Autodesk Fusion 360 part; units mm, degrees
(part 2 of 18)
sketch "8x8-User_Drawings" plane through (0, 0, 0) normal (0, 0, 1) x (1, 0, 0)
  line L0 (119.511, -144.623) -> (118.963, -144.827)
  line L1 (121.059, -143.805) -> (120.561, -144.111)
  line L2 (120.561, -144.111) -> (120.044, -144.384)
  line L3 (124.456, -132.831) -> (124.659, -133.378)
  line L4 (121.99, -143.101) -> (121.536, -143.468)
  line L5 (122.823, -142.282) -> (122.42, -142.705)
  line L6 (121.536, -143.468) -> (121.059, -143.805)
  line L7 (55.9045, -129.451) -> (55.4411, -129.079)
  line L8 (55.4411, -129.079) -> (54.954, -128.74)
  line L9 (54.4456, -128.433) -> (53.9179, -128.161)
  line L10 (54.954, -128.74) -> (54.4456, -128.433)
  line L11 (57.8006, -131.718) -> (57.4833, -131.217)
  line L12 (58.084, -132.24) -> (57.8006, -131.718)
  line L13 (57.4833, -131.217) -> (57.1334, -130.737)
  line L14 (57.1334, -130.737) -> (56.7525, -130.281)
  line L15 (56.3423, -129.852) -> (55.9045, -129.451)
  line L16 (123.544, -141.363) -> (123.199, -141.834)
  line L17 (56.7525, -130.281) -> (56.3423, -129.852)
  line L18 (124.218, -132.297) -> (124.456, -132.831)
  line L19 (53.9179, -128.161) -> (53.3734, -127.924)
  line L20 (53.3734, -127.924) -> (52.8143, -127.724)
  line L21 (52.2432, -127.561) -> (51.6626, -127.437)
  line L22 (56.453, -142.538) -> (56.8557, -142.101)
  line L23 (85.6834, -62.0285) -> (85.495, -62.5917)
  line L24 (52.8143, -127.724) -> (52.2432, -127.561)
  line L25 (123.858, -140.87) -> (123.544, -141.363)
  line L26 (56.8557, -142.101) -> (57.2286, -141.639)
  line L27 (58.3321, -132.78) -> (58.084, -132.24)
  line L28 (55.0844, -143.674) -> (55.5654, -143.326)
  line L29 (107.078, -135.288) -> (107.159, -134.71)
  line L30 (123.199, -141.834) -> (122.823, -142.282)
  line L31 (53.5182, -144.517) -> (54.0585, -144.271)
  line L32 (54.5813, -143.99) -> (55.0844, -143.674)
  line L33 (52.3945, -144.9) -> (52.9627, -144.727)
  line L34 (52.9627, -144.727) -> (53.5182, -144.517)
  line L35 (113.386, -127.609) -> (113.949, -127.454)
  line L36 (51.8162, -145.034) -> (52.3945, -144.9)
  line L37 (85.2321, -63.7491) -> (85.1587, -64.3384)
  line L38 (51.2302, -145.13) -> (51.8162, -145.034)
  line L39 (54.0585, -144.271) -> (54.5813, -143.99)
  line L40 (115.099, -127.253) -> (115.682, -127.209)
  line L41 (58.5935, -139.017) -> (58.7582, -138.447)
  line L42 (58.7582, -138.447) -> (58.8847, -137.867)
  line L43 (58.9725, -137.279) -> (59.0211, -136.687)
  line L44 (55.5654, -143.326) -> (56.0223, -142.947)
  line L45 (85.495, -62.5917) -> (85.3443, -63.166)
  line L46 (58.8847, -137.867) -> (58.9725, -137.279)
  line L47 (85.3443, -63.166) -> (85.2321, -63.7491)
  line L48 (56.0223, -142.947) -> (56.453, -142.538)
  line L49 (112.834, -127.801) -> (113.386, -127.609)
  line L50 (57.8785, -140.646) -> (58.1527, -140.119)
  line L51 (57.2286, -141.639) -> (57.57, -141.153)
  line L52 (57.57, -141.153) -> (57.8785, -140.646)
  line L53 (114.521, -127.335) -> (115.099, -127.253)
  line L54 (122.42, -142.705) -> (121.99, -143.101)
  line L55 (120.044, -144.384) -> (119.511, -144.623)
  line L56 (58.1527, -140.119) -> (58.3914, -139.576)
  line L57 (51.075, -127.351) -> (50.483, -127.304)
  line L58 (50.483, -127.304) -> (49.8893, -127.297)
  line L59 (124.781, -138.729) -> (124.602, -139.286)
  line L60 (125.125, -136.424) -> (125.095, -137.007)
  line L61 (43.5489, -130.12) -> (43.157, -130.566)
  line L62 (123.304, -130.804) -> (123.641, -131.281)
  line L63 (125.027, -137.588) -> (124.922, -138.162)
  line L64 (58.3914, -139.576) -> (58.5935, -139.017)
  line L65 (123.641, -131.281) -> (123.946, -131.78)
  line L66 (124.659, -133.378) -> (124.827, -133.938)
  line L67 (124.14, -140.359) -> (123.858, -140.87)
  line L68 (108.402, -131.454) -> (108.727, -130.969)
  line L69 (108.727, -130.969) -> (109.084, -130.506)
  line L70 (109.469, -130.066) -> (109.882, -129.653)
  line L71 (109.084, -130.506) -> (109.469, -130.066)
  line L72 (41.6834, -133.129) -> (41.495, -133.692)
  line L73 (41.9088, -132.579) -> (41.6834, -133.129)
  line L74 (107.432, -133.574) -> (107.622, -133.022)
  line L75 (107.622, -133.022) -> (107.848, -132.483)
  line L76 (108.108, -131.96) -> (108.402, -131.454)
  line L77 (109.882, -129.653) -> (110.32, -129.267)
  line L78 (110.32, -129.267) -> (110.783, -128.91)
  line L79 (110.783, -128.91) -> (111.268, -128.584)
  line L80 (107.848, -132.483) -> (108.108, -131.96)
  line L81 (111.268, -128.584) -> (111.772, -128.289)
  line L82 (121.673, -129.138) -> (122.121, -129.514)
  line L83 (59.0121, -135.657) -> (58.9531, -135.066)
  line L84 (58.8551, -134.48) -> (58.7185, -133.902)
  line L85 (59.0211, -136.687) -> (59.0318, -136.25)
  line L86 (59.0318, -136.25) -> (59.0121, -135.657)
  line L87 (58.5439, -133.335) -> (58.3321, -132.78)
  line L88 (58.7185, -133.902) -> (58.5439, -133.335)
  line L89 (58.9531, -135.066) -> (58.8551, -134.48)
  line L90 (122.543, -129.918) -> (122.938, -130.349)
  line L91 (43.9695, -129.701) -> (43.5489, -130.12)
  line L92 (125.051, -135.084) -> (125.108, -135.666)
  line L93 (124.957, -134.508) -> (125.051, -135.084)
  line L94 (125.108, -135.666) -> (125.127, -136.25)
  line L95 (41.1587, -135.438) -> (41.1245, -136.031)
  line L96 (41.2321, -134.849) -> (41.1587, -135.438)
  line L97 (41.3443, -134.266) -> (41.2321, -134.849)
  line L98 (41.495, -133.692) -> (41.3443, -134.266)
  line L99 (125.127, -136.25) -> (125.125, -136.424)
  line L100 (124.602, -139.286) -> (124.389, -139.83)
  line L101 (122.121, -129.514) -> (122.543, -129.918)
  line L102 (120.199, -128.194) -> (120.711, -128.476)
  line L103 (43.157, -130.566) -> (42.7955, -131.037)
  line L104 (119.128, -127.73) -> (119.671, -127.944)
  line L105 (41.1297, -136.625) -> (41.1742, -137.217)
  line L106 (111.772, -128.289) -> (112.295, -128.028)
  line L107 (51.6626, -127.437) -> (51.075, -127.351)
  line L108 (113.949, -127.454) -> (114.521, -127.335)
  line L109 (107.159, -134.71) -> (107.277, -134.137)
  line L110 (122.938, -130.349) -> (123.304, -130.804)
  line L111 (107.277, -134.137) -> (107.432, -133.574)
  line L112 (123.946, -131.78) -> (124.218, -132.297)
  line L113 (124.827, -133.938) -> (124.957, -134.508)
  line L114 (124.922, -138.162) -> (124.781, -138.729)
  line L115 (46.4345, -128.069) -> (45.9003, -128.329)
  line L116 (47.5484, -127.659) -> (46.9847, -127.846)
  line L117 (42.466, -131.531) -> (42.17, -132.046)
  line L118 (45.3845, -128.623) -> (44.8893, -128.951)
  line L119 (121.203, -128.792) -> (121.673, -129.138)
  line L120 (86.17, -60.9459) -> (85.9088, -61.4791)
  line L121 (46.9847, -127.846) -> (46.4345, -128.069)
  line L122 (117.43, -127.302) -> (118.005, -127.408)
  line L123 (116.85, -127.233) -> (117.43, -127.302)
  line L124 (42.17, -132.046) -> (41.9088, -132.579)
  line L125 (125.095, -137.007) -> (125.027, -137.588)
  line L126 (41.1245, -136.031) -> (41.1297, -136.625)
  line L127 (118.005, -127.408) -> (118.571, -127.551)
  line L128 (45.9003, -128.329) -> (45.3845, -128.623)
  line L129 (116.266, -127.202) -> (116.85, -127.233)
  line L130 (124.389, -139.83) -> (124.14, -140.359)
  line L131 (44.8893, -128.951) -> (44.417, -129.31)
  line L132 (48.1233, -127.511) -> (47.5484, -127.659)
  line L133 (112.295, -128.028) -> (112.834, -127.801)
  line L134 (49.2963, -127.329) -> (48.7068, -127.4)
  line L135 (119.671, -127.944) -> (120.199, -128.194)
  line L136 (49.8893, -127.297) -> (49.2963, -127.329)
  line L137 (115.682, -127.209) -> (116.266, -127.202)
  line L138 (86.466, -60.4311) -> (86.17, -60.9459)
  line L139 (120.711, -128.476) -> (121.203, -128.792)
  line L140 (48.7068, -127.4) -> (48.1233, -127.511)
  line L141 (44.417, -129.31) -> (43.9695, -129.701)
  line L142 (42.7955, -131.037) -> (42.466, -131.531)
  line L143 (85.9088, -61.4791) -> (85.6834, -62.0285)
  line L144 (118.571, -127.551) -> (119.128, -127.73)
  line L145 (120.446, -128.433) -> (119.918, -128.161)
  line L146 (122.856, -142.101) -> (123.229, -141.639)
  line L147 (123.57, -141.153) -> (123.879, -140.646)
  line L148 (123.879, -140.646) -> (124.153, -140.119)
  line L149 (121.441, -129.079) -> (120.954, -128.74)
  line L150 (120.954, -128.74) -> (120.446, -128.433)
  line L151 (123.229, -141.639) -> (123.57, -141.153)
  line L152 (121.904, -129.451) -> (121.441, -129.079)
  line L153 (107.382, -138.76) -> (107.238, -138.193)
  line L154 (122.342, -129.852) -> (121.904, -129.451)
  line L155 (125.032, -136.25) -> (125.012, -135.657)
  line L156 (125.021, -136.687) -> (125.032, -136.25)
  line L157 (124.391, -139.576) -> (124.594, -139.017)
  line L158 (124.153, -140.119) -> (124.391, -139.576)
  line L159 (124.594, -139.017) -> (124.758, -138.447)
  line L160 (124.972, -137.279) -> (125.021, -136.687)
  line L161 (117.816, -145.034) -> (118.395, -144.9)
  line L162 (122.453, -142.538) -> (122.856, -142.101)
  line L163 (109.657, -142.493) -> (110.085, -142.905)
  line L164 (124.885, -137.867) -> (124.972, -137.279)
  line L165 (114.276, -145.022) -> (114.861, -145.122)
  line L166 (115.452, -145.183) -> (116.046, -145.205)
  line L167 (116.046, -145.205) -> (116.639, -145.187)
  line L168 (110.539, -143.287) -> (111.018, -143.639)
  line L169 (110.085, -142.905) -> (110.539, -143.287)
  line L170 (114.861, -145.122) -> (115.452, -145.183)
  line L171 (123.133, -130.737) -> (122.753, -130.281)
  line L172 (124.758, -138.447) -> (124.885, -137.867)
  line L173 (117.23, -145.13) -> (117.816, -145.034)
  line L174 (116.639, -145.187) -> (117.23, -145.13)
  line L175 (111.518, -143.958) -> (112.039, -144.243)
  line L176 (108.311, -140.898) -> (108.028, -140.387)
  line L177 (108.028, -140.387) -> (107.777, -139.859)
  line L178 (120.581, -143.99) -> (121.084, -143.674)
  line L179 (123.483, -131.217) -> (123.133, -130.737)
  line L180 (107.777, -139.859) -> (107.562, -139.316)
  line L181 (108.627, -141.389) -> (108.311, -140.898)
  line L182 (124.719, -133.902) -> (124.544, -133.335)
  line L183 (108.975, -141.859) -> (108.627, -141.389)
  line L184 (125.012, -135.657) -> (124.953, -135.066)
  line L185 (120.059, -144.271) -> (120.581, -143.99)
  line L186 (108.55, -141.101) -> (108.888, -141.589)
  line L187 (113.132, -144.707) -> (113.699, -144.883)
  line L188 (122.022, -142.947) -> (122.453, -142.538)
  line L189 (112.039, -144.243) -> (112.578, -144.493)
  line L190 (112.672, -144.635) -> (112.138, -144.398)
  line L191 (119.518, -144.517) -> (120.059, -144.271)
  line L192 (108.245, -140.591) -> (108.55, -141.101)
  line L193 (110.187, -143.121) -> (109.756, -142.727)
  line L194 (113.22, -144.837) -> (112.672, -144.635)
  line L195 (109.351, -142.306) -> (108.975, -141.859)
  line L196 (111.018, -143.639) -> (111.518, -143.958)
  line L197 (113.699, -144.883) -> (114.276, -145.022)
  line L198 (118.963, -144.727) -> (119.518, -144.517)
  line L199 (110.643, -143.487) -> (110.187, -143.121)
  line L200 (124.855, -134.48) -> (124.719, -133.902)
  line L201 (107.562, -139.316) -> (107.382, -138.76)
  line L202 (123.801, -131.718) -> (123.483, -131.217)
  line L203 (112.138, -144.398) -> (111.62, -144.127)
  line L204 (107.258, -137.805) -> (107.38, -138.386)
  line L205 (114.35, -145.134) -> (113.78, -145.004)
  line L206 (121.084, -143.674) -> (121.565, -143.326)
  line L207 (124.084, -132.24) -> (123.801, -131.718)
  line L208 (107.131, -137.619) -> (107.061, -137.039)
  line L209 (111.62, -144.127) -> (111.121, -143.823)
  line L210 (108.888, -141.589) -> (109.257, -142.054)
  line L211 (124.953, -135.066) -> (124.855, -134.48)
  line L212 (109.257, -142.054) -> (109.657, -142.493)
  line L213 (117.835, -145.128) -> (117.258, -145.223)
  line L214 (116.677, -145.28) -> (116.093, -145.3)
  line L215 (117.258, -145.223) -> (116.677, -145.28)
  line L216 (121.565, -143.326) -> (122.022, -142.947)
  line L217 (115.509, -145.282) -> (114.927, -145.227)
  line L218 (107.174, -137.217) -> (107.258, -137.805)
  line L219 (116.093, -145.3) -> (115.509, -145.282)
  line L220 (107.029, -136.455) -> (107.033, -136.031)
  line L221 (107.061, -137.039) -> (107.029, -136.455)
  line L222 (112.578, -144.493) -> (113.132, -144.707)
  line L223 (118.395, -144.9) -> (118.963, -144.727)
  line L224 (109.756, -142.727) -> (109.351, -142.306)
  line L225 (113.78, -145.004) -> (113.22, -144.837)
  line L226 (114.927, -145.227) -> (114.35, -145.134)
  line L227 (122.753, -130.281) -> (122.342, -129.852)
  line L228 (107.035, -135.871) -> (107.078, -135.288)
  line L229 (107.541, -138.958) -> (107.739, -139.517)
  line L230 (118.404, -144.996) -> (117.835, -145.128)
  line L231 (124.332, -132.78) -> (124.084, -132.24)
  line L232 (107.38, -138.386) -> (107.541, -138.958)
  line L233 (111.121, -143.823) -> (110.643, -143.487)
  line L234 (124.544, -133.335) -> (124.332, -132.78)
  line L235 (107.033, -136.031) -> (107.035, -135.871)
  line L236 (107.974, -140.063) -> (108.245, -140.591)
  line L237 (118.963, -144.827) -> (118.404, -144.996)
  line L238 (107.739, -139.517) -> (107.974, -140.063)
  line L239 (107.238, -138.193) -> (107.131, -137.619)
  line L240 (109.97, -129.701) -> (109.549, -130.12)
  line L241 (118.814, -127.724) -> (118.243, -127.561)
  line L242 (109.549, -130.12) -> (109.157, -130.566)
  line L243 (130.108, -131.96) -> (130.402, -131.454)
  line L244 (130.402, -131.454) -> (130.727, -130.969)
  line L245 (110.417, -129.31) -> (109.97, -129.701)
  line L246 (129.848, -132.483) -> (130.108, -131.96)
  line L247 (111.9, -128.329) -> (111.385, -128.623)
  line L248 (129.432, -133.574) -> (129.622, -133.022)
  line L249 (111.385, -128.623) -> (110.889, -128.951)
  line L250 (114.707, -127.4) -> (114.123, -127.511)
  line L251 (129.277, -134.137) -> (129.432, -133.574)
  line L252 (112.434, -128.069) -> (111.9, -128.329)
  line L253 (108.466, -131.531) -> (108.17, -132.046)
  line L254 (107.909, -132.579) -> (107.683, -133.129)
  line L255 (108.795, -131.037) -> (108.466, -131.531)
  line L256 (115.296, -127.329) -> (114.707, -127.4)
  line L257 (112.985, -127.846) -> (112.434, -128.069)
  line L258 (129.622, -133.022) -> (129.848, -132.483)
  line L259 (129.159, -134.71) -> (129.277, -134.137)
  line L260 (119.918, -128.161) -> (119.373, -127.924)
  line L261 (119.373, -127.924) -> (118.814, -127.724)
  line L262 (110.889, -128.951) -> (110.417, -129.31)
  line L263 (107.13, -136.625) -> (107.174, -137.217)
  line L264 (115.889, -127.297) -> (115.296, -127.329)
  line L265 (107.683, -133.129) -> (107.495, -133.692)
  line L266 (107.232, -134.849) -> (107.159, -135.438)
  line L267 (129.078, -135.288) -> (129.159, -134.71)
  line L268 (118.243, -127.561) -> (117.663, -127.437)
  line L269 (114.123, -127.511) -> (113.548, -127.659)
  line L270 (117.075, -127.351) -> (116.483, -127.304)
  line L271 (107.344, -134.266) -> (107.232, -134.849)
  line L272 (108.17, -132.046) -> (107.909, -132.579)
  line L273 (116.483, -127.304) -> (115.889, -127.297)
  line L274 (113.548, -127.659) -> (112.985, -127.846)
  line L275 (117.663, -127.437) -> (117.075, -127.351)
  line L276 (109.157, -130.566) -> (108.795, -131.037)
  line L277 (107.159, -135.438) -> (107.124, -136.031)
  line L278 (107.124, -136.031) -> (107.13, -136.625)
  line L279 (107.495, -133.692) -> (107.344, -134.266)
  line L280 (100.342, -58.7519) -> (99.9045, -58.3507)
  line L281 (89.9003, -57.2286) -> (89.3845, -57.5228)
  line L282 (96.2432, -56.461) -> (95.6626, -56.3365)
  line L283 (94.483, -56.2042) -> (93.8893, -56.197)
  line L284 (96.8143, -56.6237) -> (96.2432, -56.461)
  line L285 (90.4345, -56.9692) -> (89.9003, -57.2286)
  line L286 (95.075, -56.2508) -> (94.483, -56.2042)
  line L287 (99.9045, -58.3507) -> (99.4411, -57.9794)
  line L288 (99.4411, -57.9794) -> (98.954, -57.6397)
  line L289 (86.7955, -59.9371) -> (86.466, -60.4311)
  line L290 (90.9847, -56.7458) -> (90.4345, -56.9692)
  line L291 (87.157, -59.466) -> (86.7955, -59.9371)
  line L292 (97.3734, -56.8239) -> (96.8143, -56.6237)
  line L293 (88.8893, -57.8505) -> (88.417, -58.2104)
  line L294 (89.3845, -57.5228) -> (88.8893, -57.8505)
  line L295 (98.954, -57.6397) -> (98.4456, -57.333)
  line L296 (95.6626, -56.3365) -> (95.075, -56.2508)
  line L297 (87.9695, -58.6007) -> (87.5489, -59.0199)
  line L298 (93.2963, -56.2291) -> (92.7068, -56.3004)
  line L299 (91.5484, -56.5593) -> (90.9847, -56.7458)
  line L300 (92.1233, -56.4107) -> (91.5484, -56.5593)
  line L301 (97.9179, -57.0606) -> (97.3734, -56.8239)
  line L302 (98.4456, -57.333) -> (97.9179, -57.0606)
  line L303 (87.5489, -59.0199) -> (87.157, -59.466)
  line L304 (88.417, -58.2104) -> (87.9695, -58.6007)
  line L305 (93.8893, -56.197) -> (93.2963, -56.2291)
  line L306 (92.7068, -56.3004) -> (92.1233, -56.4107)
  line L307 (142.044, -144.384) -> (141.511, -144.623)
  line L308 (146.957, -134.508) -> (147.051, -135.084)
  line L309 (147.027, -137.588) -> (146.922, -138.162)
  line L310 (147.108, -135.666) -> (147.127, -136.25)
  line L311 (140.571, -127.551) -> (141.128, -127.73)
  line L312 (145.304, -130.804) -> (145.641, -131.281)
  line L313 (145.946, -131.78) -> (146.218, -132.297)
  line L314 (146.218, -132.297) -> (146.456, -132.831)
  line L315 (145.641, -131.281) -> (145.946, -131.78)
  line L316 (146.659, -133.378) -> (146.827, -133.938)
  line L317 (135.949, -127.454) -> (136.521, -127.335)
  line L318 (137.099, -127.253) -> (137.682, -127.209)
  line L319 (138.85, -127.233) -> (139.43, -127.302)
  line L320 (133.268, -128.584) -> (133.772, -128.289)
  line L321 (130.727, -130.969) -> (131.084, -130.506)
  line L322 (146.922, -138.162) -> (146.781, -138.729)
  line L323 (143.673, -129.138) -> (144.121, -129.514)
  line L324 (147.125, -136.424) -> (147.095, -137.007)
  line L325 (141.511, -144.623) -> (140.963, -144.827)
  line L326 (144.938, -130.349) -> (145.304, -130.804)
  line L327 (144.121, -129.514) -> (144.543, -129.918)
  line L328 (146.389, -139.83) -> (146.14, -140.359)
  line L329 (144.543, -129.918) -> (144.938, -130.349)
  line L330 (146.14, -140.359) -> (145.858, -140.87)
  line L331 (138.266, -127.202) -> (138.85, -127.233)
  line L332 (141.128, -127.73) -> (141.671, -127.944)
  line L333 (135.386, -127.609) -> (135.949, -127.454)
  line L334 (134.295, -128.028) -> (134.834, -127.801)
  line L335 (144.823, -142.282) -> (144.42, -142.705)
  line L336 (144.42, -142.705) -> (143.99, -143.101)
  line L337 (145.858, -140.87) -> (145.544, -141.363)
  line L338 (147.051, -135.084) -> (147.108, -135.666)
  line L339 (143.203, -128.792) -> (143.673, -129.138)
  line L340 (146.827, -133.938) -> (146.957, -134.508)
  line L341 (140.005, -127.408) -> (140.571, -127.551)
  line L342 (143.99, -143.101) -> (143.536, -143.468)
  line L343 (147.095, -137.007) -> (147.027, -137.588)
  line L344 (142.711, -128.476) -> (143.203, -128.792)
  line L345 (147.127, -136.25) -> (147.125, -136.424)
  line L346 (146.602, -139.286) -> (146.389, -139.83)
  line L347 (142.199, -128.194) -> (142.711, -128.476)
  line L348 (142.561, -144.111) -> (142.044, -144.384)
  line L349 (137.682, -127.209) -> (138.266, -127.202)
  line L350 (139.43, -127.302) -> (140.005, -127.408)
  line L351 (146.781, -138.729) -> (146.602, -139.286)
  line L352 (146.456, -132.831) -> (146.659, -133.378)
  line L353 (134.834, -127.801) -> (135.386, -127.609)
  line L354 (136.521, -127.335) -> (137.099, -127.253)
  line L355 (131.882, -129.653) -> (132.32, -129.267)
  line L356 (143.536, -143.468) -> (143.059, -143.805)
  line L357 (131.469, -130.066) -> (131.882, -129.653)
  line L358 (132.32, -129.267) -> (132.783, -128.91)
  line L359 (145.544, -141.363) -> (145.199, -141.834)
  line L360 (131.084, -130.506) -> (131.469, -130.066)
  line L361 (141.671, -127.944) -> (142.199, -128.194)
  line L362 (145.199, -141.834) -> (144.823, -142.282)
  line L363 (132.783, -128.91) -> (133.268, -128.584)
  line L364 (143.059, -143.805) -> (142.561, -144.111)
  line L365 (133.772, -128.289) -> (134.295, -128.028)
  line L366 (101.133, -59.6368) -> (100.753, -59.1812)
  line L367 (103.012, -64.5565) -> (102.953, -63.9656)
  line L368 (100.453, -71.4378) -> (100.856, -71.0014)
  line L369 (102.332, -61.6798) -> (102.084, -61.1403)
  line L370 (97.5182, -73.4173) -> (98.0585, -73.1711)
  line L371 (93.4521, -74.0832) -> (94.0455, -74.1049)
  line L372 (94.6391, -74.0873) -> (95.2302, -74.0304)
  line L373 (102.953, -63.9656) -> (102.855, -63.38)
  line L374 (103.032, -65.15) -> (103.012, -64.5565)
  line L375 (96.9627, -73.6272) -> (97.5182, -73.4173)
  line L376 (102.719, -62.8021) -> (102.544, -62.2345)
  line L377 (101.229, -70.5393) -> (101.57, -70.0534)
  line L378 (100.753, -59.1812) -> (100.342, -58.7519)
  line L379 (100.856, -71.0014) -> (101.229, -70.5393)
  line L380 (102.758, -67.3467) -> (102.885, -66.7665)
  line L381 (96.3945, -73.7999) -> (96.9627, -73.6272)
  line L382 (99.0844, -72.574) -> (99.5654, -72.2258)
  line L383 (102.594, -67.9172) -> (102.758, -67.3467)
  line L384 (101.879, -69.546) -> (102.153, -69.0193)
  line L385 (99.5654, -72.2258) -> (100.022, -71.8465)
  line L386 (102.084, -61.1403) -> (101.801, -60.6185)
  line L387 (102.972, -66.1793) -> (103.021, -65.5875)
  line L388 (101.57, -70.0534) -> (101.879, -69.546)
  line L389 (102.391, -68.4756) -> (102.594, -67.9172)
  line L390 (102.544, -62.2345) -> (102.332, -61.6798)
  line L391 (102.855, -63.38) -> (102.719, -62.8021)
  line L392 (98.0585, -73.1711) -> (98.5813, -72.8896)
  line L393 (102.885, -66.7665) -> (102.972, -66.1793)
  line L394 (95.8162, -73.9345) -> (96.3945, -73.7999)
  line L395 (101.801, -60.6185) -> (101.483, -60.1165)
  line L396 (103.021, -65.5875) -> (103.032, -65.15)
  line L397 (95.2302, -74.0304) -> (95.8162, -73.9345)
  line L398 (102.153, -69.0193) -> (102.391, -68.4756)
  line L399 (94.0455, -74.1049) -> (94.6391, -74.0873)
  line L400 (101.483, -60.1165) -> (101.133, -59.6368)
  line L401 (98.5813, -72.8896) -> (99.0844, -72.574)
  line L402 (100.022, -71.8465) -> (100.453, -71.4378)
  line L403 (91.6987, -73.7835) -> (92.2761, -73.9221)
  line L404 (91.1318, -73.6069) -> (91.6987, -73.7835)
  line L405 (92.2761, -73.9221) -> (92.8615, -74.0221)
  line L406 (92.8615, -74.0221) -> (93.4521, -74.0832)
  line L407 (85.0332, -64.9312) -> (85.0347, -64.771)
  line L408 (85.3803, -67.2861) -> (85.541, -67.8577)
  line L409 (85.2578, -66.705) -> (85.3803, -67.2861)
  line L410 (91.9488, -56.3538) -> (92.5208, -56.2348)
  line L411 (85.3817, -67.6597) -> (85.2379, -67.0934)
  line L412 (85.9741, -68.9629) -> (86.2446, -69.4915)
  line L413 (94.2663, -56.102) -> (94.8498, -56.1331)
  line L414 (85.0612, -65.9388) -> (85.0291, -65.3553)
  line L415 (86.0276, -69.2867) -> (85.7774, -68.7587)
  line L416 (90.2951, -56.928) -> (90.8336, -56.7011)
  line L417 (93.0994, -56.1529) -> (93.682, -56.1086)
  line L418 (89.7724, -57.1892) -> (90.2951, -56.928)
  line L419 (90.5778, -73.3931) -> (91.1318, -73.6069)
  line L420 (85.1309, -66.5189) -> (85.0612, -65.9388)
  line L421 (91.3856, -56.5094) -> (91.9488, -56.3538)
  line L422 (86.2446, -69.4915) -> (86.5495, -70.001)
  line L423 (85.7774, -68.7587) -> (85.5618, -68.2156)
  line L424 (19.9088, -61.4791) -> (19.6834, -62.0285)
  line L425 (90.0392, -73.1431) -> (90.5778, -73.3931)
  line L426 (86.3113, -69.7975) -> (86.0276, -69.2867)
  line L427 (87.6569, -71.3931) -> (88.0847, -71.8049)
  line L428 (88.0847, -71.8049) -> (88.539, -72.1873)
  line L429 (92.5208, -56.2348) -> (93.0994, -56.1529)
  line L430 (85.1742, -66.1171) -> (85.2578, -66.705)
  line L431 (20.466, -60.4311) -> (20.17, -60.9459)
  line L432 (20.17, -60.9459) -> (19.9088, -61.4791)
  line L433 (88.539, -72.1873) -> (89.0175, -72.5389)
  line L434 (86.8876, -70.4892) -> (87.2572, -70.9539)
  line L435 (86.5495, -70.001) -> (86.8876, -70.4892)
  line L436 (85.0291, -65.3553) -> (85.0332, -64.9312)
  line L437 (89.0175, -72.5389) -> (89.5183, -72.8579)
  line L438 (85.541, -67.8577) -> (85.7392, -68.4175)
  line L439 (85.7392, -68.4175) -> (85.9741, -68.9629)
  line L440 (89.5183, -72.8579) -> (90.0392, -73.1431)
  line L441 (85.2379, -67.0934) -> (85.1309, -66.5189)
  line L442 (90.8336, -56.7011) -> (91.3856, -56.5094)
  line L443 (87.2572, -70.9539) -> (87.6569, -71.3931)
  line L444 (85.5618, -68.2156) -> (85.3817, -67.6597)
  line L445 (94.8498, -56.1331) -> (95.4301, -56.2018)
  line L446 (85.0347, -64.771) -> (85.078, -64.1883)
  line L447 (93.682, -56.1086) -> (94.2663, -56.102)
  line L448 (85.4315, -62.4738) -> (85.6222, -61.9215)
  line L449 (88.7829, -57.8099) -> (89.2676, -57.4835)
  line L450 (129.159, -64.3384) -> (129.124, -64.9312)
  line L451 (85.6222, -61.9215) -> (85.8482, -61.3827)
  line L452 (85.2769, -63.0373) -> (85.4315, -62.4738)
  line L453 (85.1589, -63.6096) -> (85.2769, -63.0373)
  line L454 (129.124, -64.9312) -> (129.13, -65.525)
  line L455 (87.8816, -58.5528) -> (88.3203, -58.1668)
  line L456 (89.2676, -57.4835) -> (89.7724, -57.1892)
  line L457 (88.3203, -58.1668) -> (88.7829, -57.8099)
  line L458 (129.232, -63.7491) -> (129.159, -64.3384)
  line L459 (85.078, -64.1883) -> (85.1589, -63.6096)
  line L460 (87.0836, -59.4057) -> (87.4688, -58.9664)
  line L461 (87.4688, -58.9664) -> (87.8816, -58.5528)
  line L462 (86.1085, -60.8595) -> (86.402, -60.3542)
  line L463 (86.402, -60.3542) -> (86.7274, -59.869)
  line L464 (129.13, -65.525) -> (129.174, -66.1171)
  line L465 (85.8482, -61.3827) -> (86.1085, -60.8595)
  line L466 (86.7274, -59.869) -> (87.0836, -59.4057)
  line L467 (129.344, -63.166) -> (129.232, -63.7491)
  line L468 (98.1995, -57.0936) -> (98.7108, -57.3764)
  line L469 (129.909, -61.4791) -> (129.683, -62.0285)
  line L470 (129.683, -62.0285) -> (129.495, -62.5917)
  line L471 (96.5713, -56.4506) -> (97.1275, -56.6297)
  line L472 (98.7108, -57.3764) -> (99.2028, -57.6917)
  line L473 (99.2028, -57.6917) -> (99.6734, -58.038)
  line L474 (129.495, -62.5917) -> (129.344, -63.166)
  line L475 (97.671, -56.8443) -> (98.1995, -57.0936)
  line L476 (97.1275, -56.6297) -> (97.671, -56.8443)
  line L477 (130.17, -60.9459) -> (129.909, -61.4791)
  line L478 (131.549, -59.0199) -> (131.157, -59.466)
  line L479 (96.0047, -56.3077) -> (96.5713, -56.4506)
  line L480 (132.417, -58.2104) -> (131.97, -58.6007)
  line L481 (130.795, -59.9371) -> (130.466, -60.4311)
  line L482 (95.4301, -56.2018) -> (96.0047, -56.3077)
  line L483 (131.97, -58.6007) -> (131.549, -59.0199)
  line L484 (130.466, -60.4311) -> (130.17, -60.9459)
  line L485 (131.157, -59.466) -> (130.795, -59.9371)
  line L486 (132.889, -57.8505) -> (132.417, -58.2104)
  line L487 (133.9, -57.2286) -> (133.385, -57.5228)
  line L488 (133.385, -57.5228) -> (132.889, -57.8505)
  line L489 (136.707, -56.3004) -> (136.123, -56.4107)
  line L490 (141.918, -57.0606) -> (141.373, -56.8239)
  line L491 (137.889, -56.197) -> (137.296, -56.2291)
  line L492 (139.663, -56.3365) -> (139.075, -56.2508)
  line L493 (142.954, -57.6397) -> (142.446, -57.333)
  line L494 (141.373, -56.8239) -> (140.814, -56.6237)
  line L495 (134.434, -56.9692) -> (133.9, -57.2286)
  line L496 (134.985, -56.7458) -> (134.434, -56.9692)
  line L497 (139.075, -56.2508) -> (138.483, -56.2042)
  line L498 (140.814, -56.6237) -> (140.243, -56.461)
  line L499 (138.483, -56.2042) -> (137.889, -56.197)
  line L500 (135.548, -56.5593) -> (134.985, -56.7458)
  line L501 (137.296, -56.2291) -> (136.707, -56.3004)
  line L502 (143.441, -57.9794) -> (142.954, -57.6397)
  line L503 (142.446, -57.333) -> (141.918, -57.0606)
  line L504 (140.243, -56.461) -> (139.663, -56.3365)
  line L505 (136.123, -56.4107) -> (135.548, -56.5593)
  line L506 (145.133, -59.6368) -> (144.753, -59.1812)
  line L507 (146.855, -63.38) -> (146.719, -62.8021)
  line L508 (144.753, -59.1812) -> (144.342, -58.7519)
  line L509 (146.544, -62.2345) -> (146.332, -61.6798)
  line L510 (146.719, -62.8021) -> (146.544, -62.2345)
  line L511 (107.13, -160.325) -> (107.174, -160.917)
  line L512 (147.021, -65.5875) -> (147.032, -65.15)
  line L513 (146.953, -63.9656) -> (146.855, -63.38)
  line L514 (146.972, -66.1793) -> (147.021, -65.5875)
  line L515 (143.904, -58.3507) -> (143.441, -57.9794)
  line L516 (146.084, -61.1403) -> (145.801, -60.6185)
  line L517 (145.801, -60.6185) -> (145.483, -60.1165)
  line L518 (85.1589, -134.71) -> (85.2769, -134.137)
  line L519 (146.332, -61.6798) -> (146.084, -61.1403)
  line L520 (107.124, -159.731) -> (107.13, -160.325)
  line L521 (144.342, -58.7519) -> (143.904, -58.3507)
  line L522 (147.032, -65.15) -> (147.012, -64.5565)
  line L523 (147.012, -64.5565) -> (146.953, -63.9656)
  line L524 (145.483, -60.1165) -> (145.133, -59.6368)
  line L525 (85.078, -135.288) -> (85.1589, -134.71)
  line L526 (107.683, -156.829) -> (107.495, -157.392)
  line L527 (107.909, -156.279) -> (107.683, -156.829)
  line L528 (108.466, -155.231) -> (108.17, -155.746)
  line L529 (108.795, -154.737) -> (108.466, -155.231)
  line L530 (108.17, -155.746) -> (107.909, -156.279)
  line L531 (109.97, -153.401) -> (109.549, -153.82)
  line L532 (113.548, -151.359) -> (112.985, -151.546)
  line L533 (117.075, -151.051) -> (116.483, -151.004)
  line L534 (109.549, -153.82) -> (109.157, -154.266)
  line L535 (116.483, -151.004) -> (115.889, -150.997)
  line L536 (114.123, -151.211) -> (113.548, -151.359)
  line L537 (115.296, -151.029) -> (114.707, -151.1)
  line L538 (117.663, -151.137) -> (117.075, -151.051)
  line L539 (115.889, -150.997) -> (115.296, -151.029)
  line L540 (109.157, -154.266) -> (108.795, -154.737)
  line L541 (111.9, -152.029) -> (111.385, -152.323)
  line L542 (110.889, -152.651) -> (110.417, -153.01)
  line L543 (111.385, -152.323) -> (110.889, -152.651)
  line L544 (112.985, -151.546) -> (112.434, -151.769)
  line L545 (114.707, -151.1) -> (114.123, -151.211)
  line L546 (112.434, -151.769) -> (111.9, -152.029)
  line L547 (110.417, -153.01) -> (109.97, -153.401)
  line L548 (107.232, -158.549) -> (107.159, -159.138)
  line L549 (107.495, -157.392) -> (107.344, -157.966)
  line L550 (107.344, -157.966) -> (107.232, -158.549)
  line L551 (107.159, -159.138) -> (107.124, -159.731)
  line L552 (189.858, -117.17) -> (189.544, -117.663)
  line L553 (177.62, -120.427) -> (177.121, -120.123)
  line L554 (178.138, -120.698) -> (177.62, -120.427)
  line L555 (178.672, -120.935) -> (178.138, -120.698)
  line L556 (24.138, -120.698) -> (23.6204, -120.427)
  line L557 (26.8615, -121.422) -> (27.4521, -121.483)
  line L558 (75.9179, -104.461) -> (75.3734, -104.224)
  line L559 (190.218, -108.597) -> (190.456, -109.131)
  line L560 (189.946, -108.08) -> (190.218, -108.597)
  line L561 (188.42, -119.005) -> (187.99, -119.401)
  line L562 (188.823, -118.582) -> (188.42, -119.005)
  line L563 (189.199, -118.134) -> (188.823, -118.582)
  line L564 (65.5489, -106.42) -> (65.157, -106.866)
  line L565 (26.9269, -121.527) -> (26.35, -121.434)
  line L566 (25.2202, -121.137) -> (24.672, -120.935)
  line L567 (191.012, -111.957) -> (190.953, -111.366)
  line L568 (187.441, -105.379) -> (186.954, -105.04)
  line L569 (187.904, -105.751) -> (187.441, -105.379)
  line L570 (191.032, -112.55) -> (191.012, -111.957)
  line L571 (188.342, -106.152) -> (187.904, -105.751)
  line L572 (66.417, -105.61) -> (65.9695, -106.001)
  line L573 (29.2581, -121.523) -> (28.6766, -121.58)
  line L574 (19.2379, -114.493) -> (19.1309, -113.919)
  line L575 (189.57, -117.453) -> (189.879, -116.946)
  line L576 (189.229, -117.939) -> (189.57, -117.453)
  line L577 (190.719, -110.202) -> (190.544, -109.635)
  line L578 (190.953, -111.366) -> (190.855, -110.78)
  line L579 (67.3845, -104.923) -> (66.8893, -105.251)
  line L580 (190.855, -110.78) -> (190.719, -110.202)
  line L581 (63.541, -115.258) -> (63.7392, -115.817)
  line L582 (63.3803, -114.686) -> (63.541, -115.258)
  line L583 (80.3914, -115.876) -> (80.5935, -115.317)
  line L584 (34.1207, -105.814) -> (34.5428, -106.218)
  line L585 (36.9575, -110.808) -> (37.0514, -111.384)
  line L586 (76.0585, -120.571) -> (76.5813, -120.29)
  line L587 (74.9627, -121.027) -> (75.5182, -120.817)
  line L588 (24.2951, -104.328) -> (24.8336, -104.101)
  line L589 (73.2302, -121.43) -> (73.8162, -121.334)
  line L590 (24.8336, -104.101) -> (25.3856, -103.909)
  line L591 (66.539, -119.587) -> (67.0175, -119.939)
  line L592 (74.3945, -121.2) -> (74.9627, -121.027)
  line L593 (70.8615, -121.422) -> (71.4521, -121.483)
  line L594 (73.8162, -121.334) -> (74.3945, -121.2)
  line L595 (67.0175, -119.939) -> (67.5183, -120.258)
  line L596 (37.0951, -113.307) -> (37.0274, -113.888)
  line L597 (31.671, -104.244) -> (32.1995, -104.494)
  line L598 (69.6987, -121.183) -> (70.2761, -121.322)
  line L599 (23.2676, -104.884) -> (23.7724, -104.589)
  line L600 (64.5495, -117.401) -> (64.8876, -117.889)
  line L601 (78.453, -118.838) -> (78.8557, -118.401)
  line L602 (25.9488, -103.754) -> (26.5208, -103.635)
  line L603 (72.0455, -121.505) -> (72.6391, -121.487)
  line L604 (79.2286, -117.939) -> (79.57, -117.453)
  line L605 (28.6766, -121.58) -> (28.0926, -121.6)
  line L606 (78.8557, -118.401) -> (79.2286, -117.939)
  line L607 (72.6391, -121.487) -> (73.2302, -121.43)
  line L608 (37.0514, -111.384) -> (37.1079, -111.966)
  line L609 (37.0274, -113.888) -> (36.9224, -114.462)
  line L610 (63.1742, -113.517) -> (63.2578, -114.105)
  line L611 (81.0121, -111.957) -> (80.9531, -111.366)
  line L612 (81.0318, -112.55) -> (81.0121, -111.957)
  line L613 (63.0291, -112.755) -> (63.0332, -112.331)
  line L614 (27.0994, -103.553) -> (27.682, -103.509)
  line L615 (80.9531, -111.366) -> (80.8551, -110.78)
  line L616 (78.0223, -119.247) -> (78.453, -118.838)
  line L617 (77.5654, -119.626) -> (78.0223, -119.247)
  line L618 (21.4688, -106.366) -> (21.8816, -105.953)
  line L619 (28.2663, -103.502) -> (28.8498, -103.533)
  line L620 (33.6734, -105.438) -> (34.1207, -105.814)
  line L621 (64.0276, -116.687) -> (63.7774, -116.159)
  line L622 (30.0047, -103.708) -> (30.5713, -103.851)
  line L623 (80.3321, -109.08) -> (80.084, -108.54)
  line L624 (80.7582, -114.747) -> (80.8847, -114.167)
  line L625 (79.8006, -108.018) -> (79.4833, -107.517)
  line L626 (64.9746, -118.159) -> (64.6274, -117.689)
  line L627 (80.084, -108.54) -> (79.8006, -108.018)
  line L628 (80.8847, -114.167) -> (80.9725, -113.579)
  line L629 (80.7185, -110.202) -> (80.5439, -109.635)
  line L630 (80.8551, -110.78) -> (80.7185, -110.202)
  line L631 (81.0211, -112.987) -> (81.0318, -112.55)
  line L632 (27.682, -103.509) -> (28.2663, -103.502)
  line L633 (68.5778, -120.793) -> (69.1318, -121.007)
  line L634 (23.7724, -104.589) -> (24.2951, -104.328)
  line L635 (68.138, -120.698) -> (67.6204, -120.427)
  line L636 (67.6204, -120.427) -> (67.1214, -120.123)
  line L637 (80.9725, -113.579) -> (81.0211, -112.987)
  line L638 (69.7803, -121.304) -> (69.2202, -121.137)
  line L639 (69.2202, -121.137) -> (68.672, -120.935)
  line L640 (33.2028, -105.092) -> (33.6734, -105.438)
  line L641 (80.5439, -109.635) -> (80.3321, -109.08)
  line L642 (34.9379, -106.649) -> (35.3045, -107.104)
  line L643 (33.5654, -119.626) -> (34.0223, -119.247)
  line L644 (74.4039, -121.296) -> (73.8346, -121.428)
  line L645 (34.8234, -118.582) -> (34.42, -119.005)
  line L646 (63.5618, -115.616) -> (63.3817, -115.06)
  line L647 (63.3817, -115.06) -> (63.2379, -114.493)
  line L648 (64.2446, -116.891) -> (64.5495, -117.401)
  line L649 (26.35, -121.434) -> (25.7803, -121.304)
  line L650 (184.963, -121.027) -> (185.518, -120.817)
  line L651 (25.7803, -121.304) -> (25.2202, -121.137)
  line L652 (184.395, -121.2) -> (184.963, -121.027)
  line L653 (190.391, -115.876) -> (190.594, -115.317)
  line L654 (190.153, -116.419) -> (190.391, -115.876)
  line L655 (189.879, -116.946) -> (190.153, -116.419)
  line L656 (187.565, -119.626) -> (188.022, -119.247)
  line L657 (23.1214, -120.123) -> (22.643, -119.787)
  line L658 (80.1527, -116.419) -> (80.3914, -115.876)
  line L659 (26.5208, -103.635) -> (27.0994, -103.553)
  line L660 (79.8785, -116.946) -> (80.1527, -116.419)
  line L661 (79.57, -117.453) -> (79.8785, -116.946)
  line L662 (80.5935, -115.317) -> (80.7582, -114.747)
  line L663 (25.3856, -103.909) -> (25.9488, -103.754)
  line L664 (30.5713, -103.851) -> (31.1275, -104.03)
  line L665 (70.1233, -103.811) -> (69.5484, -103.959)
  line L666 (182.639, -121.487) -> (183.23, -121.43)
  line L667 (183.23, -121.43) -> (183.816, -121.334)
  line L668 (77.0844, -119.974) -> (77.5654, -119.626)
  line L669 (76.5813, -120.29) -> (77.0844, -119.974)
  line L670 (20.5495, -117.401) -> (20.8876, -117.889)
  line L671 (183.816, -121.334) -> (184.395, -121.2)
  line L672 (75.5182, -120.817) -> (76.0585, -120.571)
  line L673 (70.2761, -121.322) -> (70.8615, -121.422)
  line L674 (69.1318, -121.007) -> (69.6987, -121.183)
  line L675 (71.4521, -121.483) -> (72.0455, -121.505)
  line L676 (181.452, -121.483) -> (182.046, -121.505)
  line L677 (182.046, -121.505) -> (182.639, -121.487)
  line L678 (20.2446, -116.891) -> (20.5495, -117.401)
  line L679 (66.0847, -119.205) -> (66.539, -119.587)
  line L680 (65.6569, -118.793) -> (66.0847, -119.205)
  line L681 (23.6204, -120.427) -> (23.1214, -120.123)
  line L682 (65.2572, -118.354) -> (65.6569, -118.793)
  line L683 (64.8876, -117.889) -> (65.2572, -118.354)
  line L684 (63.0347, -112.171) -> (63.078, -111.588)
  line L685 (22.3203, -105.567) -> (22.7829, -105.21)
  line L686 (63.2578, -114.105) -> (63.3803, -114.686)
  line L687 (173.683, -109.429) -> (173.495, -109.992)
  line L688 (19.7392, -115.817) -> (19.9741, -116.363)
  line L689 (19.9741, -116.363) -> (20.2446, -116.891)
  line L690 (63.0332, -112.331) -> (63.0347, -112.171)
  line L691 (64.3113, -117.198) -> (64.0276, -116.687)
  line L692 (63.7774, -116.159) -> (63.5618, -115.616)
  line L693 (68.672, -120.935) -> (68.138, -120.698)
  line L694 (20.7274, -107.269) -> (21.0836, -106.806)
  line L695 (34.453, -118.838) -> (34.8557, -118.401)
  line L696 (32.0585, -120.571) -> (32.5813, -120.29)
  line L697 (68.0392, -120.543) -> (68.5778, -120.793)
  line L698 (33.0587, -120.105) -> (32.5607, -120.411)
  line L699 (32.7108, -104.776) -> (33.2028, -105.092)
  line L700 (71.8893, -103.597) -> (71.2963, -103.629)
  line L701 (64.6274, -117.689) -> (64.3113, -117.198)
  line L702 (177.018, -119.939) -> (177.518, -120.258)
  line L703 (177.518, -120.258) -> (178.039, -120.543)
  line L704 (178.039, -120.543) -> (178.578, -120.793)
  line L705 (176.085, -119.205) -> (176.539, -119.587)
  line L706 (176.539, -119.587) -> (177.018, -119.939)
  line L707 (29.4301, -103.602) -> (30.0047, -103.708)
  line L708 (35.5441, -117.663) -> (35.1986, -118.134)
  line L709 (73.6626, -103.737) -> (73.075, -103.651)
  line L710 (20.1085, -108.26) -> (20.402, -107.754)
  line L711 (73.8346, -121.428) -> (73.2581, -121.523)
  line L712 (73.2581, -121.523) -> (72.6766, -121.58)
  line L713 (75.5109, -120.923) -> (74.9634, -121.127)
  line L714 (74.9634, -121.127) -> (74.4039, -121.296)
  line L715 (173.174, -113.517) -> (173.258, -114.105)
  line L716 (173.258, -114.105) -> (173.38, -114.686)
  line L717 (34.5428, -106.218) -> (34.9379, -106.649)
  line L718 (35.3045, -107.104) -> (35.6409, -107.581)
  line L719 (173.033, -112.331) -> (173.035, -112.171)
  line L720 (173.38, -114.686) -> (173.541, -115.258)
  line L721 (79.1986, -118.134) -> (78.8234, -118.582)
  line L722 (19.6222, -109.322) -> (19.8482, -108.783)
  line L723 (35.1986, -118.134) -> (34.8234, -118.582)
  line L724 (173.035, -112.171) -> (173.078, -111.588)
  line L725 (78.8234, -118.582) -> (78.42, -119.005)
  line L726 (78.42, -119.005) -> (77.9903, -119.401)
  line L727 (75.3734, -104.224) -> (74.8143, -104.024)
  line L728 (176.187, -119.421) -> (175.756, -119.027)
  line L729 (175.756, -119.027) -> (175.351, -118.606)
  line L730 (175.351, -118.606) -> (174.975, -118.159)
  line L731 (177.121, -120.123) -> (176.643, -119.787)
  line L732 (79.8585, -117.17) -> (79.5441, -117.663)
  line L733 (176.643, -119.787) -> (176.187, -119.421)
  line L734 (79.5441, -117.663) -> (79.1986, -118.134)
  line L735 (81.0951, -113.307) -> (81.0274, -113.888)
  line L736 (81.1251, -112.724) -> (81.0951, -113.307)
  line L737 (34.0223, -119.247) -> (34.453, -118.838)
  line L738 (19.2769, -110.437) -> (19.4315, -109.874)
  line L739 (67.5183, -120.258) -> (68.0392, -120.543)
  line L740 (32.5607, -120.411) -> (32.0441, -120.684)
  line L741 (32.5813, -120.29) -> (33.0844, -119.974)
  line L742 (81.1079, -111.966) -> (81.1268, -112.55)
  line L743 (81.0274, -113.888) -> (80.9224, -114.462)
  line L744 (35.6409, -107.581) -> (35.9457, -108.08)
  line L745 (77.4411, -105.379) -> (76.954, -105.04)
  line L746 (81.1268, -112.55) -> (81.1251, -112.724)
  line L747 (186.561, -120.411) -> (186.044, -120.684)
  line L748 (187.059, -120.105) -> (186.561, -120.411)
  line L749 (19.078, -111.588) -> (19.1589, -111.01)
  line L750 (36.7806, -115.029) -> (36.6024, -115.586)
  line L751 (80.2178, -108.597) -> (80.4559, -109.131)
  line L752 (186.044, -120.684) -> (185.511, -120.923)
  line L753 (79.9457, -108.08) -> (80.2178, -108.597)
  line L754 (187.536, -119.768) -> (187.059, -120.105)
  line L755 (187.99, -119.401) -> (187.536, -119.768)
  line L756 (79.6409, -107.581) -> (79.9457, -108.08)
  line L757 (78.9379, -106.649) -> (79.3045, -107.104)
  line L758 (26.2761, -121.322) -> (26.8615, -121.422)
  line L759 (79.1334, -107.037) -> (78.7525, -106.581)
  line L760 (20.0276, -116.687) -> (19.7774, -116.159)
  line L761 (79.3045, -107.104) -> (79.6409, -107.581)
  line L762 (190.827, -110.238) -> (190.957, -110.808)
  line L763 (75.1275, -104.03) -> (75.671, -104.244)
  line L764 (63.1245, -112.331) -> (63.1297, -112.925)
  line L765 (190.957, -110.808) -> (191.051, -111.384)
  line L766 (20.6274, -117.689) -> (20.3113, -117.198)
  line L767 (76.1995, -104.494) -> (76.7108, -104.776)
  line L768 (75.671, -104.244) -> (76.1995, -104.494)
  line L769 (74.5713, -103.851) -> (75.1275, -104.03)
  line L770 (74.0047, -103.708) -> (74.5713, -103.851)
  line L771 (63.232, -111.149) -> (63.1587, -111.738)
  line L772 (36.9224, -114.462) -> (36.7806, -115.029)
  line L773 (191.051, -111.384) -> (191.108, -111.966)
  line L774 (20.3113, -117.198) -> (20.0276, -116.687)
  line L775 (69.3856, -103.909) -> (69.9488, -103.754)
  line L776 (69.9488, -103.754) -> (70.5208, -103.635)
  line L777 (70.5208, -103.635) -> (71.0994, -103.553)
  line L778 (190.456, -109.131) -> (190.659, -109.678)
  line L779 (190.659, -109.678) -> (190.827, -110.238)
  line L780 (68.8336, -104.101) -> (69.3856, -103.909)
  line L781 (68.2951, -104.328) -> (68.8336, -104.101)
  line L782 (63.495, -109.992) -> (63.3443, -110.566)
  line L783 (20.9746, -118.159) -> (20.6274, -117.689)
  line L784 (64.7274, -107.269) -> (65.0836, -106.806)
  line L785 (65.4688, -106.366) -> (65.8816, -105.953)
  line L786 (65.0836, -106.806) -> (65.4688, -106.366)
  line L787 (25.6987, -121.183) -> (26.2761, -121.322)
  line L788 (33.5358, -119.768) -> (33.0587, -120.105)
  line L789 (79.4833, -107.517) -> (79.1334, -107.037)
  line L790 (64.402, -107.754) -> (64.7274, -107.269)
  line L791 (64.1085, -108.26) -> (64.402, -107.754)
  line L792 (188.938, -106.649) -> (189.304, -107.104)
  line L793 (189.304, -107.104) -> (189.641, -107.581)
  line L794 (63.9088, -108.879) -> (63.6834, -109.429)
  line L795 (21.6569, -118.793) -> (22.0847, -119.205)
  line L796 (189.641, -107.581) -> (189.946, -108.08)
  line L797 (22.0847, -119.205) -> (22.539, -119.587)
  line L798 (173.13, -112.925) -> (173.174, -113.517)
  line L799 (173.124, -112.331) -> (173.13, -112.925)
  line L800 (187.203, -105.092) -> (187.673, -105.438)
  line L801 (187.673, -105.438) -> (188.121, -105.814)
  line L802 (173.159, -111.738) -> (173.124, -112.331)
  line L803 (173.232, -111.149) -> (173.159, -111.738)
  line L804 (63.078, -111.588) -> (63.1589, -111.01)
  line L805 (35.9457, -108.08) -> (36.2178, -108.597)
  line L806 (25.1318, -121.007) -> (25.6987, -121.183)
  line L807 (78.7525, -106.581) -> (78.3423, -106.152)
  line L808 (191.125, -112.724) -> (191.095, -113.307)
  line L809 (64.466, -107.831) -> (64.17, -108.346)
  line L810 (174.466, -107.831) -> (174.17, -108.346)
  line L811 (174.795, -107.337) -> (174.466, -107.831)
  line L812 (191.095, -113.307) -> (191.027, -113.888)
  line L813 (175.157, -106.866) -> (174.795, -107.337)
  line L814 (191.027, -113.888) -> (190.922, -114.462)
  line L815 (175.549, -106.42) -> (175.157, -106.866)
  line L816 (175.97, -106.001) -> (175.549, -106.42)
  line L817 (188.121, -105.814) -> (188.543, -106.218)
  line L818 (188.543, -106.218) -> (188.938, -106.649)
  line L819 (24.5778, -120.793) -> (25.1318, -121.007)
  line L820 (20.8876, -117.889) -> (21.2572, -118.354)
  line L821 (21.2572, -118.354) -> (21.6569, -118.793)
  line L822 (179.548, -103.959) -> (178.985, -104.146)
  line L823 (180.123, -103.811) -> (179.548, -103.959)
  line L824 (37.1079, -111.966) -> (37.1268, -112.55)
  line L825 (65.157, -106.866) -> (64.7955, -107.337)
  line L826 (178.985, -104.146) -> (178.434, -104.369)
  line L827 (180.707, -103.7) -> (180.123, -103.811)
  line L828 (181.296, -103.629) -> (180.707, -103.7)
  line L829 (76.954, -105.04) -> (76.4456, -104.733)
  line L830 (184.404, -121.296) -> (183.835, -121.428)
  line L831 (65.9695, -106.001) -> (65.5489, -106.42)
  line L832 (31.1275, -104.03) -> (31.671, -104.244)
  line L833 (183.835, -121.428) -> (183.258, -121.523)
  line L834 (22.1873, -119.421) -> (21.7561, -119.027)
  line L835 (185.918, -104.461) -> (185.373, -104.224)
  line L836 (184.814, -104.024) -> (184.243, -103.861)
  line L837 (185.373, -104.224) -> (184.814, -104.024)
  line L838 (183.258, -121.523) -> (182.677, -121.58)
  line L839 (186.446, -104.733) -> (185.918, -104.461)
  line L840 (186.954, -105.04) -> (186.446, -104.733)
  line L841 (66.8893, -105.251) -> (66.417, -105.61)
  line L842 (21.7561, -119.027) -> (21.3513, -118.606)
  line L843 (191.108, -111.966) -> (191.127, -112.55)
  line L844 (36.2178, -108.597) -> (36.4559, -109.131)
  line L845 (190.084, -108.54) -> (189.801, -108.018)
  line L846 (189.801, -108.018) -> (189.483, -107.517)
  line L847 (191.127, -112.55) -> (191.125, -112.724)
  line L848 (33.0844, -119.974) -> (33.5654, -119.626)
  line L849 (29.2302, -121.43) -> (29.8162, -121.334)
  line L850 (190.544, -109.635) -> (190.332, -109.08)
  line L851 (189.483, -107.517) -> (189.133, -107.037)
  line L852 (74.8143, -104.024) -> (74.2432, -103.861)
  line L853 (174.311, -117.198) -> (174.028, -116.687)
  line L854 (174.028, -116.687) -> (173.777, -116.159)
  line L855 (173.777, -116.159) -> (173.562, -115.616)
  line L856 (21.3513, -118.606) -> (20.9746, -118.159)
  line L857 (190.332, -109.08) -> (190.084, -108.54)
  line L858 (185.511, -120.923) -> (184.963, -121.127)
  line L859 (184.963, -121.127) -> (184.404, -121.296)
  line L860 (37.1268, -112.55) -> (37.1251, -112.724)
  line L861 (67.9003, -104.629) -> (67.3845, -104.923)
  line L862 (22.643, -119.787) -> (22.1873, -119.421)
  line L863 (37.1251, -112.724) -> (37.0951, -113.307)
  line L864 (73.075, -103.651) -> (72.483, -103.604)
  line L865 (173.541, -115.258) -> (173.739, -115.817)
  line L866 (190.972, -113.579) -> (191.021, -112.987)
  line L867 (190.885, -114.167) -> (190.972, -113.579)
  line L868 (173.739, -115.817) -> (173.974, -116.363)
  line L869 (190.758, -114.747) -> (190.885, -114.167)
  line L870 (190.594, -115.317) -> (190.758, -114.747)
  line L871 (173.974, -116.363) -> (174.245, -116.891)
  line L872 (174.975, -118.159) -> (174.627, -117.689)
  line L873 (191.021, -112.987) -> (191.032, -112.55)
  line L874 (32.1995, -104.494) -> (32.7108, -104.776)
  line L875 (28.8498, -103.533) -> (29.4301, -103.602)
  line L876 (174.627, -117.689) -> (174.311, -117.198)
  line L877 (34.42, -119.005) -> (33.9903, -119.401)
  line L878 (30.9627, -121.027) -> (31.5182, -120.817)
  line L879 (188.022, -119.247) -> (188.453, -118.838)
  line L880 (68.9847, -104.146) -> (68.4345, -104.369)
  line L881 (187.084, -119.974) -> (187.565, -119.626)
  line L882 (188.856, -118.401) -> (189.229, -117.939)
  line L883 (71.2963, -103.629) -> (70.7068, -103.7)
  line L884 (188.453, -118.838) -> (188.856, -118.401)
  line L885 (36.3887, -116.13) -> (36.1404, -116.659)
  line L886 (36.6024, -115.586) -> (36.3887, -116.13)
  line L887 (63.6834, -109.429) -> (63.495, -109.992)
  line L888 (177.9, -104.629) -> (177.385, -104.923)
  line L889 (63.9741, -116.363) -> (64.2446, -116.891)
  line L890 (22.7829, -105.21) -> (23.2676, -104.884)
  line L891 (63.7392, -115.817) -> (63.9741, -116.363)
  line L892 (36.1404, -116.659) -> (35.8585, -117.17)
  line L893 (66.643, -119.787) -> (66.1873, -119.421)
  line L894 (67.1214, -120.123) -> (66.643, -119.787)
  line L895 (63.0612, -113.339) -> (63.0291, -112.755)
  line L896 (178.434, -104.369) -> (177.9, -104.629)
  line L897 (173.344, -110.566) -> (173.232, -111.149)
  line L898 (173.495, -109.992) -> (173.344, -110.566)
  line L899 (77.9045, -105.751) -> (77.4411, -105.379)
  line L900 (30.3945, -121.2) -> (30.9627, -121.027)
  line L901 (19.5618, -115.616) -> (19.3817, -115.06)
  line L902 (190.922, -114.462) -> (190.781, -115.029)
  line L903 (190.14, -116.659) -> (189.858, -117.17)
  line L904 (190.781, -115.029) -> (190.602, -115.586)
  line L905 (190.389, -116.13) -> (190.14, -116.659)
  line L906 (190.602, -115.586) -> (190.389, -116.13)
  line L907 (78.3423, -106.152) -> (77.9045, -105.751)
  line L908 (31.5182, -120.817) -> (32.0585, -120.571)
  line L909 (19.1742, -113.517) -> (19.2578, -114.105)
  line L910 (28.6391, -121.487) -> (29.2302, -121.43)
  line L911 (68.4345, -104.369) -> (67.9003, -104.629)
  line L912 (179.132, -121.007) -> (179.699, -121.183)
  line L913 (178.578, -120.793) -> (179.132, -121.007)
  line L914 (186.581, -120.29) -> (187.084, -119.974)
  line L915 (186.059, -120.571) -> (186.581, -120.29)